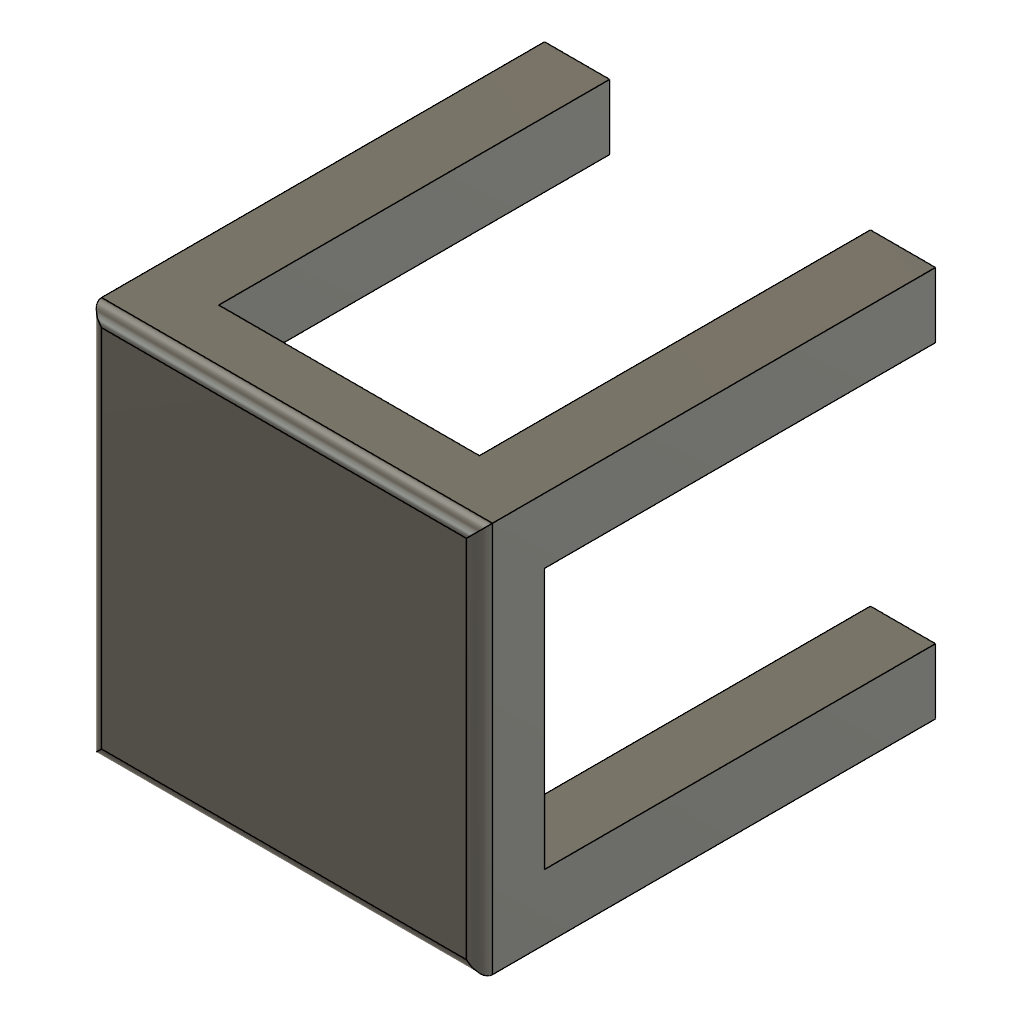
26015028 exercise 5.2(nithish R) (Autodesk Fusion 360 design; units mm, degrees)
part number: 2026-10-13-16-03-12-602
Autodesk Fusion 360 part; units mm, degrees
sketch "Sketch1" plane through (0, 0, 0) normal (0, 0, 1) x (1, 0, 0)
  line L0 (15, -15) -> (-15, -15)
  line L1 (-15, -15) -> (-15, 15)
  line L2 (-15, 15) -> (15, 15)
  line L3 (15, 15) -> (15, -15)
  line L4 (15, -15) -> (-15, 15) construction
  line L5 (-15, -15) -> (15, 15) construction
  dimension "d1" = 30
  dimension "d2" = 30
  constraint horizontal L0
  constraint perpendicular L0 L1
  constraint parallel L0 L2
  constraint parallel L1 L3
  constraint coincident L4 origin
  constraint coincident L5 origin
  measures "d1" distance of L1.end L2.end
  measures "d2" distance of L0.end L1.end
extrude "Extrude1" add sketch "Sketch1" along normal blind 5
sketch "Sketch2" plane through (0, 0, 0) normal (0, 0, -1) x (-1, 0, 0)
  line L0 (15, 15) -> (-15, 15)
  line L1 (-15, 15) -> (-15, -15)
  line L2 (-15, -15) -> (15, -15)
  line L3 (15, -15) -> (15, 15)
  line L4 (15, -15) -> (10, -15)
  line L5 (10, -15) -> (10, -10)
  line L6 (10, -10) -> (15, -10)
  line L7 (15, -10) -> (15, -15)
  line L8 (-15, -15) -> (-10, -15)
  line L9 (-10, -15) -> (-10, -10)
  line L10 (-10, -10) -> (-15, -10)
  line L11 (-15, -10) -> (-15, -15)
  line L12 (15, 15) -> (10, 15)
  line L13 (10, 15) -> (10, 10)
  line L14 (10, 10) -> (15, 10)
  line L15 (15, 10) -> (15, 15)
  line L16 (-15, 15) -> (-10, 15)
  line L17 (-10, 15) -> (-10, 10)
  line L18 (-10, 10) -> (-15, 10)
  line L19 (-15, 10) -> (-15, 15)
  dimension "d5" = 5
  dimension "d6" = 5
  dimension "d7" = 5
  dimension "d8" = 5
  dimension "d9" = 5
  dimension "d10" = 5
  dimension "d11" = 5
  dimension "d12" = 5
  constraint horizontal L4
  constraint vertical L5
  constraint horizontal L6
  constraint vertical L7
  constraint coincident L2.end L3.start
  constraint horizontal L8
  constraint vertical L9
  constraint horizontal L10
  constraint vertical L11
  constraint coincident L1.end L2.start
  constraint horizontal L12
  constraint vertical L13
  constraint horizontal L14
  constraint vertical L15
  constraint coincident L0.start L3.end
  constraint horizontal L16
  constraint vertical L17
  constraint horizontal L18
  constraint vertical L19
  constraint coincident L0.end L1.start
  measures "d5" distance of L2.end L4.end
  measures "d6" distance of L2.end L6.end
  measures "d7" distance of L1.end L8.end
  measures "d8" distance of L1.end L10.end
  measures "d9" distance of L0.start L12.end
  measures "d10" distance of L0.start L14.end
  measures "d11" distance of L0.end L16.end
  measures "d12" distance of L0.end L18.end
extrude "Extrude2" add sketch "Sketch2" along normal blind 30 contours L0 L3 L12 L13 L14 L15 | L0 L1 L16 L17 L18 L19 | L2 L3 L4 L5 L6 L7 | L1 L2 L8 L9 L10 L11
fillet "Fillet1" radius 1 4 edges at (-15, 0, 5) (0, 15, 5) (15, 0, 5) (0, -15, 5)
